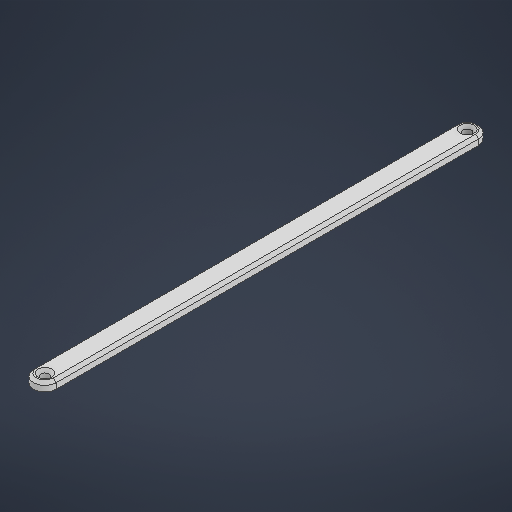
# Autodesk Inventor part: stick_2
Saved by Autodesk Inventor 2026.2 (Build 302298010, 298A)
## iProperties
Created: 2026-11-05
Part Number: stick_2
Material: Générique
Document SubType Name: Modeling
Designer: User
Density: 1 g/cm^3
Appearance: Par défaut
Author: User
Autodesk Inventor part; units mm, degrees
ref_plane "YZ Plane" through (0, 0, 0) normal (1, 0, 0) x (0, 1, 0)
ref_plane "XZ Plane" through (0, 0, 0) normal (0, 1, 0) x (-1, 0, 0)
ref_plane "XY Plane" through (0, 0, 0) normal (0, 0, 1) x (1, 0, 0)
sketch "Esquisse1" plane through (0, 0, 0) normal (0, 1, 0) x (-1, 0, 0)
  line L0 (0, 75) -> (0, -75) construction
  line L1 (-4, 75) -> (-4, -75)
  line L2 (4, -75) -> (4, 75)
  arc A0 (4, 75) -> (-4, 75) centre (0, 75) ccw
  arc A1 (-4, -75) -> (4, -75) centre (0, -75) ccw
  circle A2 centre (0, 75) radius 1.5
  circle A3 centre (0, -75) radius 1.5
  point P0 (0, 0)
  point P1 (0, 0)
  dimension "d0" = 4
  dimension "d1" = 150
  dimension "d2" = 3
  dimension "d3" = 3
  constraints: 8 end point, 4 centre point, 4 point on circle, 4 tangent, 3 coincident, 1 midpoint, 1 parallel, 1 vertical
  measures "d0" radius of A0
  measures "d1" distance of L2.start L2.end
  measures "d2" diameter of A2
  measures "d3" diameter of A3
extrude "Extrusion1" add sketch "Esquisse1" along normal blind 3
chamfer "Chanfrein1" distance 1 angle 45 6 edges at (4, 3, 0) (0, 3, -79) (-4, 3, 0) (0, 3, 79) (1.5, 3, 75) (1.5, 3, -75)
equation "\"d3\" = d2"
